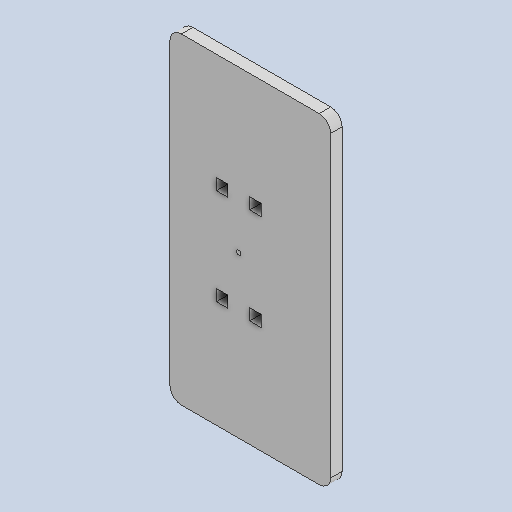
# Autodesk Inventor part: FootStepL
Saved by Autodesk Inventor 2025.2 (Build 292293000, 293)
## iProperties
Created: 2025-06-24
Part Number: FootStepL
Material: Generic
Document SubType Name: Modeling
Designer: ricoa
Density: 1 g/cm^3
Appearance: Default
Author: ricoa
Autodesk Inventor part; units mm, degrees
ref_plane "YZ Plane" through (0, 0, 0) normal (1, 0, 0) x (0, 1, 0)
ref_plane "XZ Plane" through (0, 0, 0) normal (0, 1, 0) x (-1, 0, 0)
ref_plane "XY Plane" through (0, 0, 0) normal (0, 0, 1) x (1, 0, 0)
sketch "Sketch1" plane through (0, 0, 0) normal (0, 0, 1) x (1, 0, 0)
  circle A0 centre (13.3449, -18.5) radius 1 projected
  line L0 (13.3449, -18.5) -> (-16.6551, -18.5)
  line L1 (13.3449, -18.5) -> (53.3449, -18.5)
  line L2 (53.3449, -18.5) -> (53.3449, -88.5)
  line L3 (53.3449, -88.5) -> (-16.6551, -88.5)
  line L4 (-16.6551, -88.5) -> (-16.6551, 51.5)
  line L5 (-16.6551, 51.5) -> (53.3449, 51.5)
  line L6 (53.3449, 51.5) -> (53.3449, -88.5)
  point P0 (0, 5)
  point P1 (27.75, -41.866)
  dimension "d0" = 30
  dimension "d1" = 40
  dimension "d2" = 70
  dimension "d3" = 70
  dimension "d4" = 140
  constraints: 14 end point, 3 horizontal, 2 parallel, 2 perpendicular
  measures "d0" distance of L0.start L0.end
  measures "d1" distance of L0.start L1.end
  measures "d2" distance of L1.end L2.end
  measures "d3" distance of L4.end L5.end
  measures "d4" distance of L3.end L4.end
extrude "Extrusion1" add sketch "Sketch1" along normal blind 5 contours L1 L2 L3 L4 L0 A0 | A0 L0 L4 L5 L6 L1
fillet "Fillet1" radius 5 4 edges at (53.3449, 51.5, 2.5) (-16.6551, 51.5, 2.5) (53.3449, -88.5, 2.5) (-16.6551, -88.5, 2.5)
sketch "Sketch2" plane through (0, 0, 0) normal (0, 0, -1) x (-1, 0, 0)
  line L0 (-3.5949, 0) -> (-8.5949, 0) projected
  line L1 (-8.5949, 0) -> (-8.5949, 5) projected
  line L2 (-3.5949, 5) -> (-8.5949, 5) projected
  line L3 (-3.5949, 0) -> (-3.5949, 5) projected
  line L4 (-18.0949, 0) -> (-23.0949, 0) projected
  line L5 (-23.0949, 0) -> (-23.0949, 5) projected
  line L6 (-18.0949, 5) -> (-23.0949, 5) projected
  line L7 (-18.0949, 0) -> (-18.0949, 5) projected
  line L8 (-3.5949, -41.866) -> (-8.5949, -41.866) projected
  line L9 (-8.5949, -41.866) -> (-8.5949, -36.866) projected
  line L10 (-3.5949, -36.866) -> (-8.5949, -36.866) projected
  line L11 (-3.5949, -41.866) -> (-3.5949, -36.866) projected
  line L12 (-18.0949, -41.866) -> (-23.0949, -41.866) projected
  line L13 (-23.0949, -41.866) -> (-23.0949, -36.866) projected
  line L14 (-18.0949, -36.866) -> (-23.0949, -36.866) projected
  line L15 (-18.0949, -41.866) -> (-18.0949, -36.866) projected
  point P0 (0, 0)
extrude "Extrusion2" cut sketch "Sketch2" against normal blind 10
body "Solid1"
